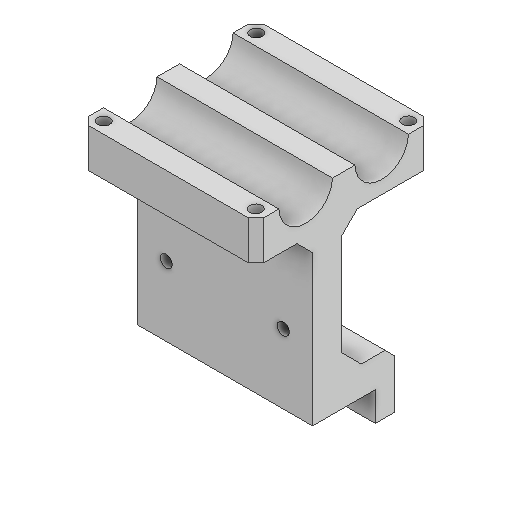
# Autodesk Inventor part: 3DP_PLA_Antenna_Boom_Log_Periodic_REVB
Saved by Autodesk Inventor 2027 (Build 310192060, 192F)
## iProperties
Created: 2026-01-18
Part Number: 3DP_PLA_Antenna_Boom_Log_Periodic_REVB
Material: Generic
Document SubType Name: Modeling
Designer: Andrzej
Density: 1 g/cm^3
Appearance: Default
Author: Andrzej
Autodesk Inventor part; units mm, degrees
ref_plane "YZ Plane" through (0, 0, 0) normal (1, 0, 0) x (0, 1, 0)
ref_plane "XZ Plane" through (0, 0, 0) normal (0, 1, 0) x (-1, 0, 0)
ref_plane "XY Plane" through (0, 0, 0) normal (0, 0, 1) x (1, 0, 0)
sketch "Sketch1" plane through (0, 0, 0) normal (0, 1, 0) x (-1, 0, 0)
  line L0 (45, 45) -> (-45, 45)
  line L1 (-45, 45) -> (-45, -45)
  line L2 (-45, -45) -> (45, -45)
  line L3 (45, -45) -> (45, 45)
  point P0 (0, 0)
  dimension "d0" = 90
  dimension "d1" = 90
  dimension "d2" = 45
  dimension "d3" = 45
  constraints: 8 end point, 2 parallel, 1 horizontal, 1 perpendicular
  measures "d0" distance of L0.start L0.end
  measures "d1" distance of L2.end L0.start
  measures "d2" distance from line of point (0, 0) L0
  measures "d3" distance from line of L3 point (0, 0)
extrude "Extrusion1" add sketch "Sketch1" along normal blind 20
sketch "Sketch2" plane through (45, 0, 45) normal (1, 0, 0) x (0, 0, -1)
  circle A0 centre (25.5, 20.5) radius 13.75
  circle A1 centre (64.5, 20.5) radius 13.75
  line L0 (0, 0) -> (90, 0) projected
  line L1 (90, 0) -> (90, 20) projected
  line L2 (0, 20) -> (90, 20) projected
  line L3 (0, 0) -> (0, 20) projected
  point P0 (45, 0)
  dimension "d6" = 27.5
  dimension "d7" = 27.5
  dimension "d8" = 0.5
  dimension "d9" = 39
  dimension "d10" = 90
  dimension "d11" = 25.5
  constraints: 2 centre point, 1 horizontal alignment
  measures "d6" diameter of A0
  measures "d7" diameter of A1
  measures "d8" distance from line of L2 A0.centre
  measures "d9" distance of A1.centre A0.centre
  measures "d10" distance between parallel lines of L1 L3
  measures "d11" distance from line of L3 A0.centre
extrude "Extrusion2" cut sketch "Sketch2" against normal through all contours A0 L2 | L2 A0 | L2 A1 | A1 L2
sketch "Sketch3" plane through (0, 0, 0) normal (0, -1, 0) x (1, 0, 0)
  line L0 (45, 45) -> (45, -45) projected
  line L1 (-45, 45) -> (45, 45) projected
  line L2 (-45, -45) -> (-45, 45) projected
  line L3 (45, -45) -> (-45, -45) projected
  line L4 (-45, 1) -> (45, 1)
  line L5 (-45, 16) -> (45, 16)
  point P0 (0, 0)
  dimension "d14" = 15
  dimension "d101" = 1
  constraints: 4 end point, 4 point on line, 2 perpendicular
  measures "d14" distance between parallel lines of L5 L4
  measures "d101" distance from line of L4 point (0, 0)
extrude "Extrusion3" add sketch "Sketch3" along normal blind 85 contours L0 L4 L2 L5
sketch "Sketch4" plane through (0, 20, 0) normal (0, 1, 0) x (1, 0, 0)
  line L0 (-45, 33.2409) -> (45, 33.2409) projected
  line L1 (45, 33.2409) -> (45, 45) projected
  line L2 (45, 45) -> (-45, 45) projected
  line L3 (-45, 45) -> (-45, 33.2409) projected
  line L4 (45, -33.2409) -> (-45, -33.2409) projected
  line L5 (-45, -33.2409) -> (-45, -45) projected
  line L6 (-45, -45) -> (45, -45) projected
  line L7 (45, -45) -> (45, -33.2409) projected
  point P0 (0, 0)
  point P1 (39, 39.1205)
  point P2 (-39, 39.1205)
  point P3 (-39, -39.1205)
  point P4 (39, -39.1205)
  dimension "d22" = 6
  dimension "d23" = 6
  dimension "d24" = 11.7591
  dimension "d25" = 11.7591
  dimension "d26" = 5.8796
  dimension "d27" = 5.8796
  constraints: 2 horizontal alignment, 2 vertical alignment
  measures "d22" distance from line of point (39, 39.12) L1
  measures "d23" distance from line of L3 point (-39, 39.12)
  measures "d24" distance between parallel lines of L2 L0
  measures "d25" distance between parallel lines of L6 L4
  measures "d26" distance from line of L2 point (39, 39.12)
  measures "d27" distance from line of L6 point (39, -39.12)
hole "Hole1" at (39, 20, -39.1205) at (-39, 20, -39.1205) at (-39, 20, 39.1205) at (39, 20, 39.1205) direction (0, -1, 0) diameter 6.2 end through all
chamfer "Chamfer1" distance 4 angle 45 4 edges at (-45, 10, -45) (-45, 10, 45) (45, 10, 45) (45, 10, -45)
chamfer "Chamfer4" distance 8 angle 45 2 edges at (0, 0, 16) (0, 0, 1)
sketch "Sketch11" plane through (45, -85, 1) normal (0, 0, -1) x (-1, 0, 0)
  line L0 (0, 77) -> (90, 77) projected
  line L1 (0, 77) -> (0, 0) projected
  line L2 (90, 0) -> (0, 0) projected
  line L3 (90, 77) -> (90, 0) projected
  line L4 (0, 0) -> (25, 0)
  line L5 (25, 0) -> (25, 15)
  line L6 (25, 15) -> (0, 15)
  line L7 (0, 15) -> (0, 0)
  line L8 (90, 0) -> (65, 0)
  line L9 (65, 0) -> (65, 15)
  line L10 (65, 15) -> (90, 15)
  line L11 (90, 15) -> (90, 0)
  point P0 (45, 85)
  point P1 (0, 15)
  point P2 (90, 15)
  point P3 (65, 0)
  dimension "d102" = 15
  dimension "d103" = 25
  dimension "d104" = 25
  constraints: 16 end point, 4 parallel, 2 horizontal, 2 perpendicular, 1 point on line
  measures "d102" distance of L4.end L5.end
  measures "d103" distance between parallel lines of L3 L9
  measures "d104" distance between parallel lines of L1 L5
extrude "Extrusion10" add sketch "Sketch11" along normal blind 17.2 contours L6 L5 L2 L1 | L3 L2 L9 L10
sketch "Sketch12" plane through (45, -85, -16.2) normal (0, 0, -1) x (-1, 0, 0)
  line L0 (0, 15) -> (0, 0) projected
  line L1 (0, 0) -> (25, 0) projected
  line L2 (25, 0) -> (25, 15) projected
  line L3 (25, 15) -> (0, 15) projected
  line L4 (65, 15) -> (65, 0) projected
  line L5 (65, 0) -> (90, 0) projected
  line L6 (90, 0) -> (90, 15) projected
  line L7 (90, 15) -> (65, 15) projected
  line L8 (25, 0) -> (0, 0)
  line L9 (0, 0) -> (0, -15)
  line L10 (0, -15) -> (25, -15)
  line L11 (25, -15) -> (25, 0)
  line L12 (90, 0) -> (65, 0)
  line L13 (65, 0) -> (65, -15)
  line L14 (65, -15) -> (90, -15)
  line L15 (90, -15) -> (90, 0)
  point P0 (45, 85)
  dimension "d107" = 15
  dimension "d108" = 15
  constraints: 16 end point, 4 parallel, 2 horizontal, 2 perpendicular
  measures "d107" distance of L10.end L1.end
  measures "d108" distance of L12.end L13.end
extrude "Extrusion11" add sketch "Sketch12" along normal blind 10
chamfer "Chamfer11" distance 10 angle 45 2 edges at (-32.5, -70, 1) (32.5, -70, 1)
chamfer "Chamfer12" distance 5 angle 45 2 edges at (32.5, -70, -26.2) (-32.5, -70, -26.2)
sketch "Sketch13" plane through (0, -85, 0) normal (0, -1, 0) x (1, 0, 0)
  circle A0 centre (0, 0) radius 7.5
  dimension "d117" = 15
  constraints: 1 centre point, 1 coincident
  measures "d117" diameter of A0
extrude "Extrusion12" cut sketch "Sketch13" against normal blind 70
chamfer "Chamfer13" distance 6 angle 45 1 edges at (0, -15, 7.5)
sketch "Sketch14" plane through (-45, -85, 16) normal (0, 0, 1) x (1, 0, 0)
  line L0 (0, 77) -> (90, 77) projected
  line L1 (0, 77) -> (0, 0) projected
  line L2 (90, 0) -> (0, 0) projected
  line L3 (90, 77) -> (90, 0) projected
  point P0 (45, 85)
  point P1 (15, 35.674)
  point P2 (75, 35.674)
  dimension "d123" = 35.674
  dimension "d124" = 15
  dimension "d125" = 15
  constraints: 1 horizontal alignment
  measures "d123" distance from line of L2 point (15, 35.674)
  measures "d124" distance from line of L1 point (15, 35.674)
  measures "d125" distance from line of L3 point (75, 35.674)
hole "Hole3" at (30, -49.326, 16) at (-30, -49.326, 16) direction (0, 0, -1) diameter 6.2 end through all
equation "\"d1\" = d0"
equation "\"d2\" = 0.5 * d1"
equation "\"d3\" = 0.5 * d0"
equation "\"d11\" = -0.5 * d9 + 0.5 * d10"
equation "\"d23\" = d22"
equation "\"d26\" = 0.5 * d24"
equation "\"d27\" = 0.5 * d25"
equation "\"d104\" = d103"
equation "\"d108\" = d107"
body "Solid1"
